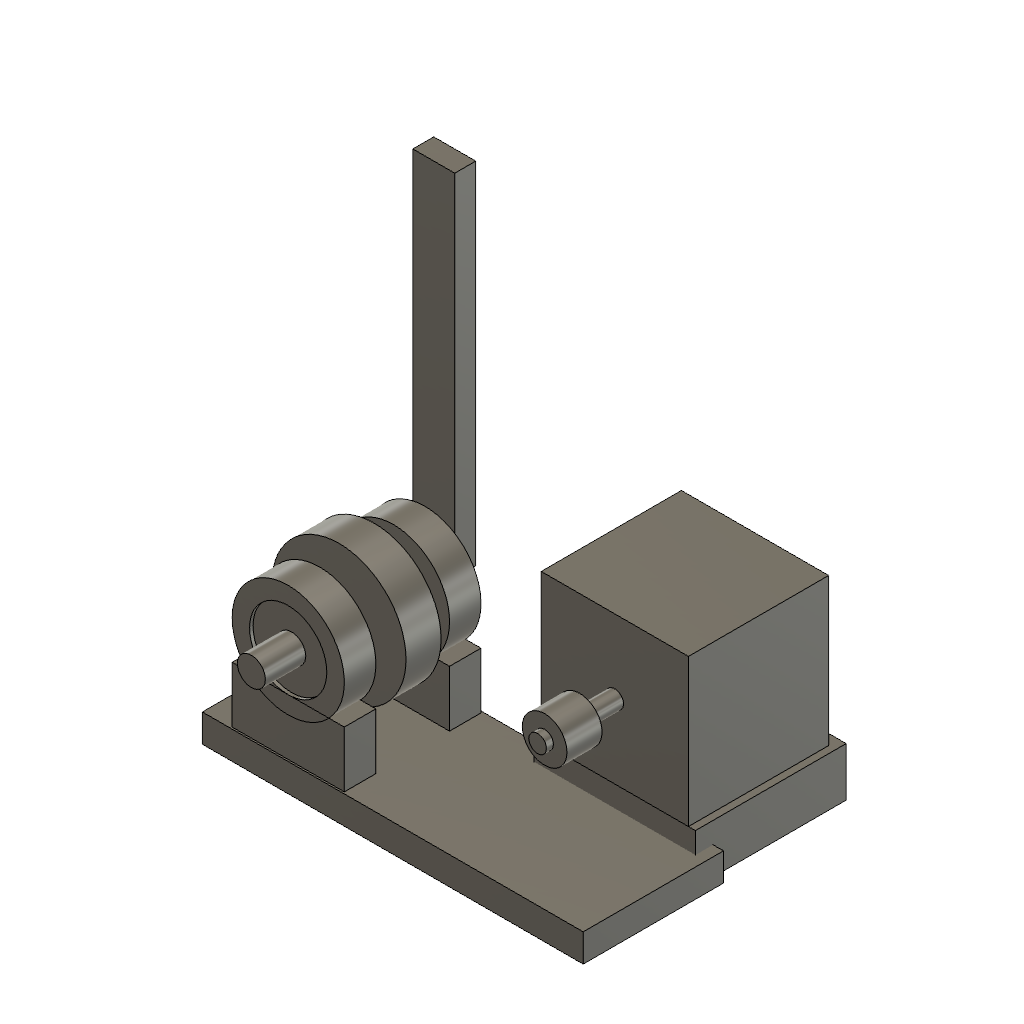
belt-joint-envelopes (Autodesk Fusion 360 design; units mm, degrees)
part number: 2026-11-06-12-58-57-791
part number: 2026-11-06-12-58-58-158
part number: 2026-11-06-12-58-58-170
part number: 2026-11-06-12-58-58-185
part number: 2026-11-06-12-58-58-203
part number: 2026-11-06-12-58-58-219
part number: 2026-11-06-12-58-58-237
part number: 2026-11-06-12-58-58-256
part number: 2026-11-06-12-58-58-273
part number: 2026-11-06-12-58-58-296
part number: 2026-11-06-12-58-58-321
part number: 2026-11-06-12-58-58-341
part number: 2026-11-06-12-58-58-362
part number: 2026-11-06-12-58-58-382
part number: 2026-11-06-12-58-58-405
Autodesk Fusion 360 part; units mm, degrees
sketch "Metal output shaft envelope section" plane through (0, 0, 0) normal (0, 0, 1) x (1, 0, 0) in component "Metal output shaft envelope"
  circle A0 centre (0, 0) radius 4
  dimension "d14" = 8
  constraint coincident A0.centre origin
  measures "d14" diameter of A0
extrude "Metal output shaft envelope length" add sketch "Metal output shaft envelope section" along normal blind 60 makes body 1 in component "Metal output shaft envelope"
sketch "608 bearing A envelope section" plane through (0, 0, 0) normal (0, 0, 1) x (1, 0, 0) in component "608 bearing A envelope"
  circle A0 centre (0, 0) radius 11
  circle A1 centre (0, 0) radius 4
  dimension "d17" = 22
  dimension "d18" = 8
  constraint coincident A0.centre A1.centre
  measures "d17" diameter of A0
  measures "d18" diameter of A1
extrude "608 bearing A envelope length" add sketch "608 bearing A envelope section" along normal blind 7 separate body makes body 2 in component "608 bearing A envelope"
sketch "Housing A envelope section" plane through (0, 0, 0) normal (0, 0, 1) x (1, 0, 0) in component "Housing A envelope"
  circle A0 centre (0, 0) radius 16
  circle A1 centre (0, 0) radius 11
  dimension "d21" = 32
  dimension "d22" = 22
  constraint coincident A0.centre A1.centre
  measures "d21" diameter of A0
  measures "d22" diameter of A1
extrude "Housing A envelope length" add sketch "Housing A envelope section" along normal blind 9 separate body makes body 3 in component "Housing A envelope"
sketch "Housing A foot envelope footprint" plane through (0, 0, 0) normal (0, 0, 1) x (1, 0, 0) in component "Housing A foot envelope"
  line L0 (0, 0) -> (32, 0)
  line L1 (32, 0) -> (32, 16)
  line L2 (32, 16) -> (0, 16)
  line L3 (0, 16) -> (0, 0)
extrude "Housing A foot envelope thickness" add sketch "Housing A foot envelope footprint" along normal blind 9 separate body makes body 4 in component "Housing A foot envelope"
sketch "608 bearing B envelope section" plane through (0, 0, 0) normal (0, 0, 1) x (1, 0, 0) in component "608 bearing B envelope"
  circle A0 centre (0, 0) radius 11
  circle A1 centre (0, 0) radius 4
  dimension "d27" = 22
  dimension "d28" = 8
  constraint coincident A0.centre A1.centre
  measures "d27" diameter of A0
  measures "d28" diameter of A1
extrude "608 bearing B envelope length" add sketch "608 bearing B envelope section" along normal blind 7 separate body makes body 5 in component "608 bearing B envelope"
sketch "Housing B envelope section" plane through (0, 0, 0) normal (0, 0, 1) x (1, 0, 0) in component "Housing B envelope"
  circle A0 centre (0, 0) radius 16
  circle A1 centre (0, 0) radius 11
  dimension "d31" = 32
  dimension "d32" = 22
  constraint coincident A0.centre A1.centre
  measures "d31" diameter of A0
  measures "d32" diameter of A1
extrude "Housing B envelope length" add sketch "Housing B envelope section" along normal blind 9 separate body makes body 6 in component "Housing B envelope"
sketch "Housing B foot envelope footprint" plane through (0, 0, 0) normal (0, 0, 1) x (1, 0, 0) in component "Housing B foot envelope"
  line L0 (0, 0) -> (32, 0)
  line L1 (32, 0) -> (32, 16)
  line L2 (32, 16) -> (0, 16)
  line L3 (0, 16) -> (0, 0)
extrude "Housing B foot envelope thickness" add sketch "Housing B foot envelope footprint" along normal blind 9 separate body makes body 7 in component "Housing B foot envelope"
sketch "60T PITCH CYLINDER no teeth section" plane through (0, 0, 0) normal (0, 0, 1) x (1, 0, 0) in component "60T PITCH CYLINDER no teeth"
  circle A0 centre (0, 0) radius 19.0986
  circle A1 centre (0, 0) radius 4
  dimension "d37" = 38.1972
  dimension "d38" = 8
  constraint coincident A0.centre A1.centre
  measures "d37" diameter of A0
  measures "d38" diameter of A1
extrude "60T PITCH CYLINDER no teeth length" add sketch "60T PITCH CYLINDER no teeth section" along normal blind 10 separate body makes body 8 in component "60T PITCH CYLINDER no teeth"
sketch "20T PITCH CYLINDER no teeth section" plane through (0, 0, 0) normal (0, 0, 1) x (1, 0, 0) in component "20T PITCH CYLINDER no teeth"
  circle A0 centre (0, 0) radius 6.3662
  circle A1 centre (0, 0) radius 2.5
  dimension "d41" = 12.7324
  dimension "d42" = 5
  constraint coincident A0.centre A1.centre
  measures "d41" diameter of A0
  measures "d42" diameter of A1
extrude "20T PITCH CYLINDER no teeth length" add sketch "20T PITCH CYLINDER no teeth section" along normal blind 10 separate body makes body 9 in component "20T PITCH CYLINDER no teeth"
sketch "Motor body GENERIC envelope footprint" plane through (0, 0, 0) normal (0, 0, 1) x (1, 0, 0) in component "Motor body GENERIC envelope"
  line L0 (0, 0) -> (42, 0)
  line L1 (42, 0) -> (42, 42)
  line L2 (42, 42) -> (0, 42)
  line L3 (0, 42) -> (0, 0)
extrude "Motor body GENERIC envelope thickness" add sketch "Motor body GENERIC envelope footprint" along normal blind 40 separate body makes body 10 in component "Motor body GENERIC envelope"
sketch "Motor bracket envelope no fasteners footprint" plane through (0, 0, 0) normal (0, 0, 1) x (1, 0, 0) in component "Motor bracket envelope no fasteners"
  line L0 (0, 0) -> (46, 0)
  line L1 (46, 0) -> (46, 14)
  line L2 (46, 14) -> (0, 14)
  line L3 (0, 14) -> (0, 0)
extrude "Motor bracket envelope no fasteners thickness" add sketch "Motor bracket envelope no fasteners footprint" along normal blind 43 separate body makes body 11 in component "Motor bracket envelope no fasteners"
sketch "Motor shaft GENERIC envelope section" plane through (0, 0, 0) normal (0, 0, 1) x (1, 0, 0) in component "Motor shaft GENERIC envelope"
  circle A0 centre (0, 0) radius 2.5
  dimension "d49" = 5
  constraint coincident A0.centre origin
  measures "d49" diameter of A0
extrude "Motor shaft GENERIC envelope length" add sketch "Motor shaft GENERIC envelope section" along normal blind 22 separate body makes body 12 in component "Motor shaft GENERIC envelope"
sketch "Arm clamp envelope no fasteners footprint" plane through (0, 0, 0) normal (0, 0, 1) x (1, 0, 0) in component "Arm clamp envelope no fasteners"
  line L0 (0, 0) -> (12, 0)
  line L1 (12, 0) -> (12, 100)
  line L2 (12, 100) -> (0, 100)
  line L3 (0, 100) -> (0, 0)
extrude "Arm clamp envelope no fasteners thickness" add sketch "Arm clamp envelope no fasteners footprint" along normal blind 6 separate body makes body 13 in component "Arm clamp envelope no fasteners"
sketch "Base envelope no mounts footprint" plane through (0, 0, 0) normal (0, 0, 1) x (1, 0, 0) in component "Base envelope no mounts"
  line L0 (0, 0) -> (108.6115, 0)
  line L1 (108.6115, 0) -> (108.6115, 8)
  line L2 (108.6115, 8) -> (0, 8)
  line L3 (0, 8) -> (0, 0)
extrude "Base envelope no mounts thickness" add sketch "Base envelope no mounts footprint" along normal blind 40 separate body makes body 14 in component "Base envelope no mounts"
sketch "Belt tangent reference at z0 (actual belt plane z15)" plane through (0, 0, 0) normal (0, 0, 1) x (1, 0, 0)
  line L0 (4.1489, -18.6425) -> (59.9945, -6.2142) construction
  line L1 (4.1489, 18.6425) -> (59.9945, 6.2142) construction
component "Metal output shaft envelope" placed x (1, 0, 0) y (0, 1, 0) z (0, 0, 1) at (0, 0, -15)
component "608 bearing A envelope" placed x (1, 0, 0) y (0, 1, 0) z (0, 0, 1) at (0, 0, -3.5)
component "Housing A envelope" placed x (1, 0, 0) y (0, 1, 0) z (0, 0, 1) at (0, 0, -4.5)
component "Housing A foot envelope" placed x (1, 0, 0) y (0, 1, 0) z (0, 0, 1) at (-16, -27, -4.5)
component "608 bearing B envelope" placed x (1, 0, 0) y (0, 1, 0) z (0, 0, 1) at (0, 0, 26.5)
component "Housing B envelope" placed x (1, 0, 0) y (0, 1, 0) z (0, 0, 1) at (0, 0, 25.5)
component "Housing B foot envelope" placed x (1, 0, 0) y (0, 1, 0) z (0, 0, 1) at (-16, -27, 25.5)
component "60T PITCH CYLINDER no teeth" placed x (1, 0, 0) y (0, 1, 0) z (0, 0, 1) at (0, 0, 10)
component "20T PITCH CYLINDER no teeth" placed x (1, 0, 0) y (0, 1, 0) z (0, 0, 1) at (58.6115, 0, 10)
component "Motor body GENERIC envelope" placed x (1, 0, 0) y (0, 1, 0) z (0, 0, 1) at (37.6115, -21, -40)
component "Motor bracket envelope no fasteners" placed x (1, 0, 0) y (0, 1, 0) z (0, 0, 1) at (35.6115, -35, -43)
component "Motor shaft GENERIC envelope" placed x (1, 0, 0) y (0, 1, 0) z (0, 0, 1) at (58.6115, 0, 0)
component "Arm clamp envelope no fasteners" placed x (1, 0, 0) y (0, 1, 0) z (0, 0, 1) at (-6, 0, -13)
component "Base envelope no mounts" placed x (1, 0, 0) y (0, 1, 0) z (0, 0, 1) at (-24, -35, -5)
equation "pitch = 2 mm" comment "Study reference input; envelope positions require manual regeneration"
equation "motor_teeth = 20" comment "Study reference input; envelope positions require manual regeneration"
equation "output_teeth = 60" comment "Study reference input; envelope positions require manual regeneration"
equation "belt_pitch_length = 200 mm" comment "Study reference input; envelope positions require manual regeneration"
equation "center_distance = 58.61153060046303 mm" comment "Study reference input; envelope positions require manual regeneration"
equation "shaft_diameter = 8 mm" comment "Study reference input; envelope positions require manual regeneration"
equation "bearing_od = 22 mm" comment "Study reference input; envelope positions require manual regeneration"
equation "bearing_width = 7 mm" comment "Study reference input; envelope positions require manual regeneration"
equation "bearing_spacing = 30 mm" comment "Study reference input; envelope positions require manual regeneration"
equation "belt_plane = 15 mm" comment "Study reference input; envelope positions require manual regeneration"
equation "pulley_envelope_width = 10 mm" comment "Study reference input; envelope positions require manual regeneration"
equation "installation_travel = 4 mm" comment "Study reference input; envelope positions require manual regeneration"
equation "arm_length = 100 mm" comment "Study reference input; envelope positions require manual regeneration"
named bodies: "Metal output shaft envelope", "608 bearing A envelope", "Housing A envelope", "Housing A foot envelope", "608 bearing B envelope", "Housing B envelope", "Housing B foot envelope", "60T PITCH CYLINDER no teeth", "20T PITCH CYLINDER no teeth", "Motor body GENERIC envelope", "Motor bracket envelope no fasteners", "Motor shaft GENERIC envelope", "Arm clamp envelope no fasteners", "Base envelope no mounts"
